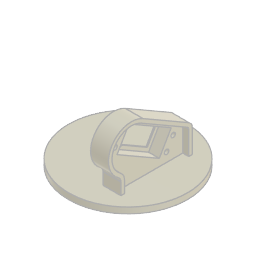
Shoulder (Autodesk Fusion 360 design; units mm, degrees)
Autodesk Fusion 360 part; units mm, degrees
sketch "Sketch1" plane through (0, 0, 0) normal (0, 0, 1) x (1, 0, 0)
  circle A0 centre (0, 0) radius 50
  circle A1 centre (0, 0) radius 2.5
  circle A2 centre (0, 6.85) radius 1.5
  circle A3 centre (0, -6.85) radius 1.5
  dimension "d43" = 100
  dimension "d44" = 5
  dimension "d45" = 3
  dimension "d46" = 3
  dimension "d47" = 6.85
  dimension "d48" = 6.85
  constraint coincident A0.centre A1.centre
  measures "d43" diameter of A0
  measures "d44" diameter of A1
  measures "d45" diameter of A2
  measures "d46" diameter of A3
  measures "d47" distance of A0.centre A2.centre
  measures "d48" distance of A0.centre A3.centre
extrude "Extrude1" add sketch "Sketch1" along normal blind 5
ref_plane "WorkPlane1" through (9.0605, -13.7504, 5) normal (1, 0, 0) x (0, 0, 1)
sketch "Sketch2" plane through (9.0605, 0, 0) normal (1, 0, 0) x (0, 1, 0)
  line L0 (-30, 0) -> (30, 0)
  line L1 (-30, 0) -> (-30, 15)
  line L2 (30, 0) -> (30, 25)
  line L3 (27.5, 29.3301) -> (-11.4711, 51.8301)
  arc A0 (-11.4711, 51.8301) -> (-32.1596, 19.1149) centre (-21.156, 35.0555) ccw
  arc A1 (30, 25) -> (27.5, 29.3301) centre (25, 25) ccw
  arc A2 (-30, 15) -> (-32.1596, 19.1149) centre (-35, 15) ccw
  arc A3 (-27, 15) -> (-30.4553, 21.5838) centre (-35, 15) ccw
  arc A4 (-12.9712, 49.2321) -> (-30.4553, 21.5838) centre (-21.156, 35.0555) ccw
  line L4 (26, 26.7321) -> (-12.9712, 49.2321)
  arc A5 (27, 25) -> (26, 26.7321) centre (25, 25) ccw
  line L5 (27, 3) -> (27, 25)
  line L6 (-27, 3) -> (27, 3)
  line L7 (-27, 3) -> (-27, 15)
  line L8 (-18.2454, 48.8131) -> (17.2616, 28.3131)
  line L9 (-18.2454, 48.8131) -> (-28.2454, 31.4926)
  line L10 (-28.2454, 31.4926) -> (7.2616, 10.9926)
  line L11 (17.2616, 28.3131) -> (7.2616, 10.9926)
  circle A6 centre (-24.3925, 47.1659) radius 2.25
  circle A7 centre (18.9087, 22.1659) radius 2.25
  line L12 (-23.2454, 40.1528) -> (-27.37, 42.5341)
  circle A8 centre (-29.8925, 37.6397) radius 2.25
  circle A9 centre (13.4087, 12.6397) radius 2.25
  point P0 (-30, 17.8228)
  point P1 (30, 27.8868)
  dimension "d52" = 60
  dimension "d57" = 120
  dimension "d59" = 5
  dimension "d60" = -3
  dimension "d65" = 41
  dimension "d67" = 20
  dimension "d71" = 25
  dimension "d74" = 3
  dimension "d75" = 41
  dimension "d76" = 15
  dimension "d77" = 45
  dimension "d78" = 4.5
  dimension "d79" = 4.5
  dimension "d80" = 4.5
  dimension "d81" = 4.5
  dimension "d82" = 4.5
  constraint midpoint L0 origin
  constraint horizontal L0
  constraint perpendicular L0 L1
  constraint perpendicular L0 L2
  constraint tangent L3 A0
  constraint coincident P1 L2
  constraint coincident P1 L3
  constraint tangent L2 A1
  constraint tangent L3 A1
  constraint coincident P0 L1
  constraint coincident P0 A0
  constraint tangent L1 A2
  constraint tangent A0 A2
  constraint equal A1 A2
  constraint parallel L4 L8
  constraint perpendicular L8 L9
  constraint parallel L8 L10
  constraint midpoint L9 L12.start
  constraint perpendicular L9 L12
  constraint symmetric A6 L12 A8
  constraint symmetric A7 L12 A9
  measures "d52" distance of L0.start L0.end
  measures "d57" angle of L2 L3
  measures "d59" radius of A1
  measures "d65" distance of L8.start L8.end
  measures "d67" distance of L8.start L9.end
  measures "d71" distance of L0.end L2.end
  measures "d74" distance of L4 L8
  measures "d75" distance of L9.end L10.end
  measures "d76" distance of L0.start L1.end
  measures "d77" distance of L3.end L3.start
  measures "d78" diameter of A6
  measures "d79" distance of L9 A6.centre
  measures "d80" diameter of A7
  measures "d81" distance of L11 A7.centre
  measures "d82" distance of L8 A7.centre
extrude "Extrude2" add sketch "Sketch2" along normal blind 15 contours L0 L1 L2 L3 A0 A1 A2
extrude "Extrude3" add sketch "Sketch2" along normal blind 10 contours A3 A4 L4 A5 L5 L6 L7 | L8 L9 L10 L11 | A6 | A7 | A8 | A9
sketch "Sketch3" plane through (19.0605, 0, 0) normal (1, 0, 0) x (0, 1, 0)
  line L0 (-27, 5) -> (27, 5)
  line L1 (27, 5) -> (27, 25)
  arc A0 (27, 25) -> (26, 26.7321) centre (25, 25) ccw
  line L2 (26, 26.7321) -> (-12.9712, 49.2321)
  arc A1 (-12.9712, 49.2321) -> (-30.4553, 21.5838) centre (-21.156, 35.0555) ccw
  arc A2 (-27, 15) -> (-30.4553, 21.5838) centre (-35, 15) ccw
  line L3 (-27, 15) -> (-27, 5)
  line L4 (17.2616, 28.3131) -> (7.2616, 10.9926)
  line L5 (-18.2454, 48.8131) -> (17.2616, 28.3131)
  line L6 (-18.2454, 48.8131) -> (-28.2454, 31.4926)
  line L7 (-28.2454, 31.4926) -> (7.2616, 10.9926)
  circle A3 centre (13.4087, 12.6397) radius 2.25
  circle A4 centre (18.9087, 22.1659) radius 2.25
  circle A5 centre (-29.8925, 37.6397) radius 2.25
  circle A6 centre (-24.3925, 47.1659) radius 2.25
  line L8 (13.1635, 27.215) -> (6.1635, 15.0906)
  line L9 (-14.2981, 26.9041) -> (6.1635, 15.0906)
  line L10 (-7.2981, 39.0285) -> (13.1635, 27.215)
  arc A7 (-7.2981, 39.0285) -> (-14.2981, 26.9041) centre (-14.1522, 34.9028) ccw
  dimension "d91" = 16
  dimension "d93" = 10.5
  dimension "d94" = 7
  measures "d91" diameter of A7
  measures "d93" distance of L6 A7.centre
  measures "d94" distance of L10 A7.centre
extrude "Extrude4" cut sketch "Sketch3" against normal blind 9 contours L4 L5 L6 L7 | L8 L9 L10 A7
extrude "Extrude5" cut sketch "Sketch3" against normal blind 5 contours A3 | A4 | A5 | A6
thread "Thread1" "ISO Metric profile 4.5 M4.5x0.75 M4.5x0.75 6H" major diameter 4.6131 minor diameter 3.7831 pitch 0.75 angle 60 resizes the face on face at (15.7271, 21.1559, 22.0538) on face at (15.7271, -26.6314, 46.9419) on face at (15.7271, 15.6559, 12.5275) on face at (15.7271, -27.6453, 37.5275)
extrude "Extrude6" cut sketch "Sketch3" against normal blind 30 contours L8 L9 L10 A7
